Autodesk Fusion 360 part; units mm, degrees
(part 4 of 7)
  spline S126 degree 5 poles (34.1517, -31.5311) (34.1614, -31.5251) (34.1809, -31.5132) (34.2101, -31.4951) (34.2489, -31.471) (34.2972, -31.4407) (34.3454, -31.4102) (34.3934, -31.3796) (34.4413, -31.3489) (34.4891, -31.318) (34.5366, -31.2869) (34.584, -31.2557) (34.6313, -31.2244) (34.6784, -31.1929) (34.7253, -31.1613) (34.772, -31.1295) (34.8186, -31.0975) (34.865, -31.0655) (34.9112, -31.0332) (34.9573, -31.0008) (35.0032, -30.9683) (35.0489, -30.9356) (35.0944, -30.9027) (35.1398, -30.8697) (35.185, -30.8365) (35.23, -30.8032) (35.2748, -30.7697) (35.3194, -30.7361) (35.3638, -30.7023) (35.4081, -30.6683) (35.4521, -30.6342) (35.4959, -30.5999) (35.5396, -30.5654) (35.583, -30.5308) (35.6263, -30.496) (35.6693, -30.4611) (35.7121, -30.426) (35.7548, -30.3907) (35.7971, -30.3552) (35.8393, -30.3196) (35.8813, -30.2838) (35.923, -30.2478) (35.9645, -30.2116) (36.0058, -30.1753) (36.0468, -30.1387) (36.0876, -30.102) (36.1282, -30.0651) (36.1685, -30.028) (36.2085, -29.9907) (36.2483, -29.9533) (36.2879, -29.9156) (36.3271, -29.8777) (36.3661, -29.8396) (36.4048, -29.8014) (36.4432, -29.7629) (36.4775, -29.7281) (36.5039, -29.7009) (36.5226, -29.6815) (36.5338, -29.6698) (36.5375, -29.666) knots -1 -1 -1 -1 -1 -1 -0.985714 -0.971429 -0.957143 -0.942857 -0.928571 -0.914286 -0.9 -0.885714 -0.871429 -0.857143 -0.842857 -0.828571 -0.814286 -0.8 -0.785714 -0.771429 -0.757143 -0.742857 -0.728571 -0.714286 -0.7 -0.685714 -0.671429 -0.657143 -0.642857 -0.628571 -0.614286 -0.6 -0.585714 -0.571429 -0.557143 -0.542857 -0.528571 -0.514286 -0.5 -0.485714 -0.471429 -0.457143 -0.442857 -0.428571 -0.414286 -0.4 -0.385714 -0.371429 -0.357143 -0.342857 -0.328571 -0.314286 -0.3 -0.285714 -0.271429 -0.257143 -0.242857 -0.228571 -0.221564 -0.221564 -0.221564 -0.221564 -0.221564 -0.221564
  spline S127 degree 3 poles (37.152, -29.5804) (37.0958, -29.5474) (37.0338, -29.5257) (36.9049, -29.5074) (36.8392, -29.5109) (36.7308, -29.5383) (36.6874, -29.5561) (36.6066, -29.6031) (36.5698, -29.6322) (36.5375, -29.666) knots 0 0 0 0 0.019532 0.019532 0.039064 0.039064 0.053081 0.053081 0.067098 0.067098 0.067098 0.067098
  arc A64 (37.152, -29.5804) -> (37.5866, -29.8313) centre (54.5011, -0.0327) ccw
  spline S128 degree 3 poles (37.8197, -30.4063) (37.838, -30.3438) (37.8438, -30.2783) (37.8301, -30.1488) (37.8107, -30.086) (37.7576, -29.9876) (37.7298, -29.9498) (37.6644, -29.883) (37.6272, -29.8544) (37.5866, -29.8313) knots 0 0 0 0 0.019532 0.019532 0.039064 0.039064 0.053081 0.053081 0.067098 0.067098 0.067098 0.067098
  spline S129 degree 5 poles (37.8197, -30.4063) (37.8182, -30.4114) (37.8137, -30.4269) (37.8062, -30.4528) (37.7959, -30.4893) (37.7829, -30.5363) (37.7688, -30.5888) (37.755, -30.6415) (37.7415, -30.6943) (37.7283, -30.7472) (37.7155, -30.8003) (37.7029, -30.8535) (37.6906, -30.9068) (37.6787, -30.9603) (37.667, -31.0139) (37.6556, -31.0675) (37.6445, -31.1213) (37.6336, -31.1753) (37.6231, -31.2293) (37.6128, -31.2834) (37.6027, -31.3377) (37.593, -31.392) (37.5835, -31.4465) (37.5742, -31.501) (37.5652, -31.5557) (37.5564, -31.6104) (37.5479, -31.6653) (37.5397, -31.7202) (37.5317, -31.7752) (37.5239, -31.8303) (37.5164, -31.8855) (37.5091, -31.9408) (37.502, -31.9962) (37.4952, -32.0517) (37.4886, -32.1072) (37.4822, -32.1628) (37.4761, -32.2185) (37.4702, -32.2743) (37.4645, -32.3302) (37.459, -32.3861) (37.4538, -32.4422) (37.4488, -32.4982) (37.444, -32.5544) (37.4394, -32.6106) (37.435, -32.667) (37.4308, -32.7233) (37.4269, -32.7798) (37.4232, -32.8363) (37.4196, -32.8929) (37.4163, -32.9495) (37.4132, -33.0062) (37.4103, -33.063) (37.4077, -33.1199) (37.4052, -33.1768) (37.4029, -33.2337) (37.4008, -33.2908) (37.3993, -33.3364) (37.3983, -33.3707) (37.3977, -33.3936) (37.3973, -33.405) knots 0.221564 0.221564 0.221564 0.221564 0.221564 0.221564 0.228571 0.242857 0.257143 0.271429 0.285714 0.3 0.314286 0.328571 0.342857 0.357143 0.371429 0.385714 0.4 0.414286 0.428571 0.442857 0.457143 0.471429 0.485714 0.5 0.514286 0.528571 0.542857 0.557143 0.571429 0.585714 0.6 0.614286 0.628571 0.642857 0.657143 0.671429 0.685714 0.7 0.714286 0.728571 0.742857 0.757143 0.771429 0.785714 0.8 0.814286 0.828571 0.842857 0.857143 0.871429 0.885714 0.9 0.914286 0.928571 0.942857 0.957143 0.971429 0.985714 1 1 1 1 1 1
  arc A65 (37.3973, -33.405) -> (38.4371, -33.9178) centre (54.5011, -0.0327) ccw
  spline S130 degree 5 poles (38.4371, -33.9178) (38.446, -33.9106) (38.4637, -33.8961) (38.4903, -33.8745) (38.5256, -33.8455) (38.5696, -33.8091) (38.6134, -33.7726) (38.6571, -33.736) (38.7005, -33.6993) (38.7438, -33.6624) (38.7869, -33.6254) (38.8298, -33.5883) (38.8726, -33.5511) (38.9152, -33.5137) (38.9575, -33.4762) (38.9997, -33.4386) (39.0418, -33.4009) (39.0836, -33.363) (39.1252, -33.325) (39.1667, -33.2868) (39.2079, -33.2486) (39.249, -33.2102) (39.2898, -33.1717) (39.3305, -33.133) (39.3709, -33.0942) (39.4112, -33.0553) (39.4512, -33.0163) (39.4911, -32.9771) (39.5307, -32.9378) (39.5701, -32.8983) (39.6094, -32.8588) (39.6483, -32.819) (39.6871, -32.7792) (39.7257, -32.7392) (39.764, -32.6991) (39.8021, -32.6588) (39.84, -32.6184) (39.8776, -32.5778) (39.915, -32.5371) (39.9522, -32.4963) (39.9891, -32.4553) (40.0258, -32.4142) (40.0623, -32.3729) (40.0984, -32.3315) (40.1344, -32.2899) (40.17, -32.2482) (40.2054, -32.2063) (40.2405, -32.1643) (40.2754, -32.1221) (40.3099, -32.0797) (40.3442, -32.0372) (40.3782, -31.9946) (40.4118, -31.9517) (40.4452, -31.9087) (40.4783, -31.8655) (40.5077, -31.8266) (40.5303, -31.7962) (40.5464, -31.7745) (40.5559, -31.7615) (40.5591, -31.7572) knots -1 -1 -1 -1 -1 -1 -0.985714 -0.971429 -0.957143 -0.942857 -0.928571 -0.914286 -0.9 -0.885714 -0.871429 -0.857143 -0.842857 -0.828571 -0.814286 -0.8 -0.785714 -0.771429 -0.757143 -0.742857 -0.728571 -0.714286 -0.7 -0.685714 -0.671429 -0.657143 -0.642857 -0.628571 -0.614286 -0.6 -0.585714 -0.571429 -0.557143 -0.542857 -0.528571 -0.514286 -0.5 -0.485714 -0.471429 -0.457143 -0.442857 -0.428571 -0.414286 -0.4 -0.385714 -0.371429 -0.357143 -0.342857 -0.328571 -0.314286 -0.3 -0.285714 -0.271429 -0.257143 -0.242857 -0.228571 -0.221564 -0.221564 -0.221564 -0.221564 -0.221564 -0.221564
  spline S131 degree 3 poles (41.1571, -31.5921) (41.0972, -31.5667) (41.0328, -31.5533) (40.9026, -31.552) (40.838, -31.564) (40.7341, -31.6054) (40.6933, -31.6286) (40.6194, -31.6858) (40.5867, -31.7195) (40.5591, -31.7572) knots 0 0 0 0 0.019532 0.019532 0.039064 0.039064 0.053081 0.053081 0.067098 0.067098 0.067098 0.067098
  arc A66 (41.1571, -31.5921) -> (41.6208, -31.7841) centre (54.5011, -0.0327) ccw
  spline S132 degree 3 poles (41.927, -32.3238) (41.9369, -32.2594) (41.9342, -32.1937) (41.9037, -32.0672) (41.8762, -32.0074) (41.8108, -31.9168) (41.7782, -31.8829) (41.7047, -31.8253) (41.6641, -31.8017) (41.6208, -31.7841) knots 0 0 0 0 0.019532 0.019532 0.039064 0.039064 0.053081 0.053081 0.067098 0.067098 0.067098 0.067098
  spline S133 degree 5 poles (41.927, -32.3238) (41.9262, -32.329) (41.9237, -32.345) (41.9197, -32.3717) (41.9142, -32.4092) (41.9075, -32.4575) (41.9003, -32.5114) (41.8935, -32.5654) (41.887, -32.6196) (41.8809, -32.6738) (41.8751, -32.7281) (41.8695, -32.7824) (41.8643, -32.8369) (41.8594, -32.8915) (41.8549, -32.9461) (41.8506, -33.0008) (41.8466, -33.0556) (41.8429, -33.1105) (41.8394, -33.1654) (41.8363, -33.2204) (41.8334, -33.2755) (41.8308, -33.3307) (41.8285, -33.3859) (41.8265, -33.4412) (41.8247, -33.4966) (41.8231, -33.552) (41.8219, -33.6075) (41.8208, -33.663) (41.8201, -33.7186) (41.8196, -33.7743) (41.8193, -33.83) (41.8193, -33.8858) (41.8195, -33.9416) (41.82, -33.9975) (41.8207, -34.0534) (41.8216, -34.1094) (41.8228, -34.1654) (41.8243, -34.2215) (41.8259, -34.2776) (41.8278, -34.3338) (41.8299, -34.39) (41.8322, -34.4463) (41.8348, -34.5026) (41.8376, -34.5589) (41.8406, -34.6153) (41.8439, -34.6718) (41.8473, -34.7283) (41.851, -34.7848) (41.8549, -34.8413) (41.859, -34.8979) (41.8633, -34.9546) (41.8679, -35.0112) (41.8726, -35.0679) (41.8776, -35.1247) (41.8828, -35.1815) (41.8882, -35.2383) (41.8926, -35.2838) (41.8961, -35.3179) (41.8984, -35.3406) (41.8996, -35.352) knots 0.221564 0.221564 0.221564 0.221564 0.221564 0.221564 0.228571 0.242857 0.257143 0.271429 0.285714 0.3 0.314286 0.328571 0.342857 0.357143 0.371429 0.385714 0.4 0.414286 0.428571 0.442857 0.457143 0.471429 0.485714 0.5 0.514286 0.528571 0.542857 0.557143 0.571429 0.585714 0.6 0.614286 0.628571 0.642857 0.657143 0.671429 0.685714 0.7 0.714286 0.728571 0.742857 0.757143 0.771429 0.785714 0.8 0.814286 0.828571 0.842857 0.857143 0.871429 0.885714 0.9 0.914286 0.928571 0.942857 0.957143 0.971429 0.985714 1 1 1 1 1 1
  arc A67 (41.8996, -35.352) -> (42.9974, -35.7247) centre (54.5011, -0.0327) ccw
  spline S134 degree 5 poles (42.9974, -35.7247) (43.0053, -35.7164) (43.021, -35.6997) (43.0445, -35.6748) (43.0758, -35.6414) (43.1146, -35.5996) (43.1533, -35.5577) (43.1918, -35.5157) (43.2301, -35.4736) (43.2682, -35.4314) (43.3061, -35.3891) (43.3438, -35.3467) (43.3813, -35.3042) (43.4187, -35.2616) (43.4558, -35.2189) (43.4927, -35.1761) (43.5294, -35.1332) (43.566, -35.0902) (43.6023, -35.0471) (43.6384, -35.0039) (43.6743, -34.9606) (43.71, -34.9172) (43.7455, -34.8736) (43.7807, -34.83) (43.8158, -34.7863) (43.8506, -34.7424) (43.8852, -34.6985) (43.9196, -34.6545) (43.9538, -34.6103) (43.9877, -34.5661) (44.0214, -34.5217) (44.0549, -34.4772) (44.0881, -34.4327) (44.1211, -34.388) (44.1539, -34.3432) (44.1864, -34.2983) (44.2187, -34.2533) (44.2507, -34.2082) (44.2825, -34.1629) (44.314, -34.1176) (44.3453, -34.0721) (44.3763, -34.0266) (44.407, -33.9809) (44.4375, -33.9351) (44.4677, -33.8892) (44.4976, -33.8432) (44.5272, -33.797) (44.5565, -33.7508) (44.5856, -33.7044) (44.6143, -33.6579) (44.6427, -33.6113) (44.6708, -33.5645) (44.6986, -33.5177) (44.7261, -33.4707) (44.7533, -33.4235) (44.7773, -33.3811) (44.7958, -33.348) (44.8089, -33.3244) (44.8167, -33.3102) (44.8192, -33.3056) knots -1 -1 -1 -1 -1 -1 -0.985714 -0.971429 -0.957143 -0.942857 -0.928571 -0.914286 -0.9 -0.885714 -0.871429 -0.857143 -0.842857 -0.828571 -0.814286 -0.8 -0.785714 -0.771429 -0.757143 -0.742857 -0.728571 -0.714286 -0.7 -0.685714 -0.671429 -0.657143 -0.642857 -0.628571 -0.614286 -0.6 -0.585714 -0.571429 -0.557143 -0.542857 -0.528571 -0.514286 -0.5 -0.485714 -0.471429 -0.457143 -0.442857 -0.428571 -0.414286 -0.4 -0.385714 -0.371429 -0.357143 -0.342857 -0.328571 -0.314286 -0.3 -0.285714 -0.271429 -0.257143 -0.242857 -0.228571 -0.221564 -0.221564 -0.221564 -0.221564 -0.221564 -0.221564
  spline S135 degree 3 poles (45.3906, -33.0638) (45.3279, -33.0465) (45.2623, -33.0416) (45.1331, -33.0573) (45.0706, -33.0776) (44.9729, -33.1322) (44.9356, -33.1606) (44.8698, -33.227) (44.8417, -33.2646) (44.8192, -33.3056) knots 0 0 0 0 0.019532 0.019532 0.039064 0.039064 0.053081 0.053081 0.067098 0.067098 0.067098 0.067098
  arc A68 (45.3906, -33.0638) -> (45.8754, -33.1937) centre (54.5011, -0.0327) ccw
  spline S136 degree 3 poles (46.2494, -33.6888) (46.2508, -33.6237) (46.2395, -33.5589) (46.1928, -33.4374) (46.1578, -33.3818) (46.081, -33.3004) (46.0444, -33.2711) (45.9639, -33.2235) (45.9206, -33.2055) (45.8754, -33.1937) knots 0 0 0 0 0.019532 0.019532 0.039064 0.039064 0.053081 0.053081 0.067098 0.067098 0.067098 0.067098
  spline S137 degree 5 poles (46.2494, -33.6888) (46.2493, -33.6941) (46.2489, -33.7102) (46.2484, -33.7372) (46.2479, -33.7751) (46.2475, -33.8239) (46.2474, -33.8783) (46.2477, -33.9327) (46.2484, -33.9872) (46.2494, -34.0418) (46.2507, -34.0964) (46.2523, -34.151) (46.2543, -34.2057) (46.2565, -34.2604) (46.2591, -34.3152) (46.262, -34.37) (46.2652, -34.4248) (46.2687, -34.4797) (46.2725, -34.5346) (46.2765, -34.5896) (46.2809, -34.6446) (46.2855, -34.6996) (46.2904, -34.7547) (46.2956, -34.8098) (46.301, -34.8649) (46.3067, -34.92) (46.3127, -34.9752) (46.319, -35.0304) (46.3255, -35.0856) (46.3322, -35.1409) (46.3392, -35.1961) (46.3465, -35.2514) (46.354, -35.3068) (46.3618, -35.3621) (46.3698, -35.4175) (46.378, -35.4728) (46.3865, -35.5282) (46.3952, -35.5836) (46.4042, -35.6391) (46.4134, -35.6945) (46.4228, -35.75) (46.4325, -35.8055) (46.4424, -35.861) (46.4525, -35.9165) (46.4629, -35.972) (46.4735, -36.0275) (46.4843, -36.0831) (46.4953, -36.1386) (46.5065, -36.1942) (46.518, -36.2498) (46.5297, -36.3054) (46.5416, -36.361) (46.5537, -36.4166) (46.566, -36.4722) (46.5786, -36.5278) (46.5913, -36.5834) (46.6017, -36.6279) (46.6096, -36.6613) (46.6149, -36.6835) (46.6175, -36.6947) knots 0.221564 0.221564 0.221564 0.221564 0.221564 0.221564 0.228571 0.242857 0.257143 0.271429 0.285714 0.3 0.314286 0.328571 0.342857 0.357143 0.371429 0.385714 0.4 0.414286 0.428571 0.442857 0.457143 0.471429 0.485714 0.5 0.514286 0.528571 0.542857 0.557143 0.571429 0.585714 0.6 0.614286 0.628571 0.642857 0.657143 0.671429 0.685714 0.7 0.714286 0.728571 0.742857 0.757143 0.771429 0.785714 0.8 0.814286 0.828571 0.842857 0.857143 0.871429 0.885714 0.9 0.914286 0.928571 0.942857 0.957143 0.971429 0.985714 1 1 1 1 1 1
  arc A69 (46.6175, -36.6947) -> (47.7546, -36.9208) centre (54.5011, -0.0327) ccw
  spline S138 degree 5 poles (47.7546, -36.9208) (47.7613, -36.9116) (47.7747, -36.893) (47.7948, -36.8652) (47.8214, -36.8281) (47.8544, -36.7816) (47.8873, -36.735) (47.92, -36.6883) (47.9525, -36.6416) (47.9847, -36.5948) (48.0168, -36.5479) (48.0487, -36.5009) (48.0803, -36.4539) (48.1118, -36.4068) (48.143, -36.3596) (48.174, -36.3124) (48.2048, -36.265) (48.2354, -36.2176) (48.2658, -36.1701) (48.296, -36.1226) (48.3259, -36.0749) (48.3556, -36.0272) (48.3851, -35.9795) (48.4144, -35.9316) (48.4434, -35.8837) (48.4723, -35.8357) (48.5008, -35.7876) (48.5292, -35.7394) (48.5573, -35.6912) (48.5852, -35.6429) (48.6128, -35.5945) (48.6402, -35.546) (48.6673, -35.4975) (48.6942, -35.4489) (48.7208, -35.4002) (48.7472, -35.3515) (48.7734, -35.3026) (48.7992, -35.2537) (48.8248, -35.2047) (48.8502, -35.1557) (48.8752, -35.1065) (48.9, -35.0573) (48.9245, -35.008) (48.9487, -34.9586) (48.9727, -34.9092) (48.9963, -34.8596) (49.0197, -34.81) (49.0427, -34.7603) (49.0654, -34.7106) (49.0878, -34.6607) (49.1099, -34.6108) (49.1317, -34.5608) (49.1532, -34.5107) (49.1743, -34.4605) (49.195, -34.4102) (49.2134, -34.365) (49.2274, -34.3298) (49.2372, -34.3046) (49.2431, -34.2896) (49.245, -34.2846) knots -1 -1 -1 -1 -1 -1 -0.985714 -0.971429 -0.957143 -0.942857 -0.928571 -0.914286 -0.9 -0.885714 -0.871429 -0.857143 -0.842857 -0.828571 -0.814286 -0.8 -0.785714 -0.771429 -0.757143 -0.742857 -0.728571 -0.714286 -0.7 -0.685714 -0.671429 -0.657143 -0.642857 -0.628571 -0.614286 -0.6 -0.585714 -0.571429 -0.557143 -0.542857 -0.528571 -0.514286 -0.5 -0.485714 -0.471429 -0.457143 -0.442857 -0.428571 -0.414286 -0.4 -0.385714 -0.371429 -0.357143 -0.342857 -0.328571 -0.314286 -0.3 -0.285714 -0.271429 -0.257143 -0.242857 -0.228571 -0.221564 -0.221564 -0.221564 -0.221564 -0.221564 -0.221564
  spline S139 degree 3 poles (49.78, -33.9704) (49.7155, -33.9614) (49.6499, -33.9651) (49.5238, -33.9975) (49.4645, -34.0259) (49.3748, -34.0927) (49.3415, -34.1257) (49.2849, -34.2001) (49.2619, -34.2411) (49.245, -34.2846) knots 0 0 0 0 0.019532 0.019532 0.039064 0.039064 0.053081 0.053081 0.067098 0.067098 0.067098 0.067098
  arc A70 (49.78, -33.9704) -> (50.2775, -34.0359) centre (54.5011, -0.0327) ccw
  spline S140 degree 3 poles (50.713, -34.4779) (50.7059, -34.4132) (50.6863, -34.3504) (50.6241, -34.236) (50.5821, -34.1855) (50.4954, -34.1149) (50.4552, -34.0906) (50.3692, -34.0539) (50.3239, -34.0417) (50.2775, -34.0359) knots 0 0 0 0 0.019532 0.019532 0.039064 0.039064 0.053081 0.053081 0.067098 0.067098 0.067098 0.067098
  spline S141 degree 5 poles (50.713, -34.4779) (50.7135, -34.4832) (50.7153, -34.4992) (50.7183, -34.5261) (50.7228, -34.5637) (50.7287, -34.6121) (50.7358, -34.6661) (50.7432, -34.72) (50.7509, -34.7739) (50.759, -34.8279) (50.7675, -34.8818) (50.7762, -34.9358) (50.7853, -34.9898) (50.7947, -35.0437) (50.8044, -35.0977) (50.8144, -35.1516) (50.8247, -35.2056) (50.8353, -35.2596) (50.8463, -35.3135) (50.8575, -35.3675) (50.8689, -35.4214) (50.8807, -35.4754) (50.8928, -35.5293) (50.9051, -35.5833) (50.9177, -35.6372) (50.9306, -35.6911) (50.9437, -35.7451) (50.9571, -35.799) (50.9707, -35.8529) (50.9846, -35.9068) (50.9988, -35.9607) (51.0132, -36.0145) (51.0279, -36.0684) (51.0428, -36.1222) (51.058, -36.1761) (51.0734, -36.2299) (51.089, -36.2837) (51.1049, -36.3375) (51.121, -36.3913) (51.1374, -36.4451) (51.154, -36.4988) (51.1708, -36.5526) (51.1879, -36.6063) (51.2052, -36.66) (51.2227, -36.7137) (51.2404, -36.7674) (51.2584, -36.8211) (51.2765, -36.8747) (51.2949, -36.9283) (51.3136, -36.9819) (51.3324, -37.0355) (51.3515, -37.0891) (51.3707, -37.1426) (51.3902, -37.1961) (51.4099, -37.2497) (51.4298, -37.3031) (51.4459, -37.3459) (51.4581, -37.378) (51.4662, -37.3993) (51.4703, -37.41) knots 0.221564 0.221564 0.221564 0.221564 0.221564 0.221564 0.228571 0.242857 0.257143 0.271429 0.285714 0.3 0.314286 0.328571 0.342857 0.357143 0.371429 0.385714 0.4 0.414286 0.428571 0.442857 0.457143 0.471429 0.485714 0.5 0.514286 0.528571 0.542857 0.557143 0.571429 0.585714 0.6 0.614286 0.628571 0.642857 0.657143 0.671429 0.685714 0.7 0.714286 0.728571 0.742857 0.757143 0.771429 0.785714 0.8 0.814286 0.828571 0.842857 0.857143 0.871429 0.885714 0.9 0.914286 0.928571 0.942857 0.957143 0.971429 0.985714 1 1 1 1 1 1
  arc A71 (51.4703, -37.41) -> (52.6272, -37.4859) centre (54.5011, -0.0327) ccw
  spline S142 degree 5 poles (52.6272, -37.4859) (52.6326, -37.4758) (52.6435, -37.4557) (52.6597, -37.4255) (52.6813, -37.3852) (52.708, -37.3347) (52.7345, -37.2843) (52.7608, -37.2337) (52.7869, -37.1832) (52.8128, -37.1325) (52.8385, -37.0819) (52.8639, -37.0312) (52.8892, -36.9804) (52.9142, -36.9296) (52.939, -36.8787) (52.9636, -36.8278) (52.988, -36.7769) (53.0121, -36.7259) (53.036, -36.6748) (53.0597, -36.6238) (53.0832, -36.5726) (53.1064, -36.5214) (53.1294, -36.4702) (53.1522, -36.419) (53.1748, -36.3676) (53.1971, -36.3163) (53.2191, -36.2649) (53.2409, -36.2134) (53.2625, -36.162) (53.2838, -36.1104) (53.3049, -36.0588) (53.3257, -36.0072) (53.3463, -35.9556) (53.3666, -35.9039) (53.3867, -35.8521) (53.4065, -35.8003) (53.426, -35.7485) (53.4453, -35.6966) (53.4643, -35.6447) (53.483, -35.5928) (53.5014, -35.5408) (53.5195, -35.4887) (53.5374, -35.4367) (53.555, -35.3846) (53.5723, -35.3324) (53.5892, -35.2802) (53.6059, -35.228) (53.6223, -35.1757) (53.6383, -35.1234) (53.654, -35.071) (53.6694, -35.0186) (53.6845, -34.9662) (53.6992, -34.9137) (53.7136, -34.8612) (53.7276, -34.8087) (53.7399, -34.7615) (53.7492, -34.7247) (53.7557, -34.6985) (53.7595, -34.6828) (53.7608, -34.6777) knots -1 -1 -1 -1 -1 -1 -0.985714 -0.971429 -0.957143 -0.942857 -0.928571 -0.914286 -0.9 -0.885714 -0.871429 -0.857143 -0.842857 -0.828571 -0.814286 -0.8 -0.785714 -0.771429 -0.757143 -0.742857 -0.728571 -0.714286 -0.7 -0.685714 -0.671429 -0.657143 -0.642857 -0.628571 -0.614286 -0.6 -0.585714 -0.571429 -0.557143 -0.542857 -0.528571 -0.514286 -0.5 -0.485714 -0.471429 -0.457143 -0.442857 -0.428571 -0.414286 -0.4 -0.385714 -0.371429 -0.357143 -0.342857 -0.328571 -0.314286 -0.3 -0.285714 -0.271429 -0.257143 -0.242857 -0.228571 -0.221564 -0.221564 -0.221564 -0.221564 -0.221564 -0.221564
  spline S143 degree 3 poles (54.2502, -34.2963) (54.185, -34.2958) (54.1205, -34.3081) (53.9996, -34.3566) (53.9446, -34.3924) (53.8644, -34.4704) (53.8356, -34.5075) (53.7892, -34.5887) (53.7719, -34.6323) (53.7608, -34.6777) knots 0 0 0 0 0.019532 0.019532 0.039064 0.039064 0.053081 0.053081 0.067098 0.067098 0.067098 0.067098
  arc A72 (54.2502, -34.2963) -> (54.752, -34.2963) centre (54.5011, -0.0327) ccw
  spline S144 degree 3 poles (55.2414, -34.6777) (55.2259, -34.6144) (55.1983, -34.5548) (55.1217, -34.4495) (55.0735, -34.4048) (54.9783, -34.3461) (54.9352, -34.3273) (54.8452, -34.3021) (54.7987, -34.2959) (54.752, -34.2963) knots 0 0 0 0 0.019532 0.019532 0.039064 0.039064 0.053081 0.053081 0.067098 0.067098 0.067098 0.067098
  spline S145 degree 5 poles (55.2414, -34.6777) (55.2426, -34.6828) (55.2465, -34.6985) (55.253, -34.7247) (55.2623, -34.7615) (55.2745, -34.8087) (55.2886, -34.8612) (55.3029, -34.9137) (55.3177, -34.9662) (55.3327, -35.0186) (55.3481, -35.071) (55.3638, -35.1234) (55.3799, -35.1757) (55.3962, -35.228) (55.4129, -35.2802) (55.4299, -35.3324) (55.4472, -35.3846) (55.4647, -35.4367) (55.4826, -35.4887) (55.5007, -35.5408) (55.5192, -35.5928) (55.5379, -35.6447) (55.5569, -35.6966) (55.5761, -35.7485) (55.5957, -35.8003) (55.6155, -35.8521) (55.6355, -35.9039) (55.6558, -35.9556) (55.6764, -36.0072) (55.6972, -36.0588) (55.7183, -36.1104) (55.7396, -36.162) (55.7612, -36.2134) (55.783, -36.2649) (55.8051, -36.3163) (55.8274, -36.3676) (55.8499, -36.419) (55.8727, -36.4702) (55.8957, -36.5214) (55.9189, -36.5726) (55.9424, -36.6238) (55.9661, -36.6748) (55.99, -36.7259) (56.0142, -36.7769) (56.0385, -36.8278) (56.0631, -36.8787) (56.0879, -36.9296) (56.113, -36.9804) (56.1382, -37.0312) (56.1637, -37.0819) (56.1893, -37.1325) (56.2152, -37.1832) (56.2413, -37.2337) (56.2676, -37.2843) (56.2941, -37.3347) (56.3209, -37.3852) (56.3424, -37.4255) (56.3586, -37.4557) (56.3695, -37.4758) (56.375, -37.4859) knots 0.221564 0.221564 0.221564 0.221564 0.221564 0.221564 0.228571 0.242857 0.257143 0.271429 0.285714 0.3 0.314286 0.328571 0.342857 0.357143 0.371429 0.385714 0.4 0.414286 0.428571 0.442857 0.457143 0.471429 0.485714 0.5 0.514286 0.528571 0.542857 0.557143 0.571429 0.585714 0.6 0.614286 0.628571 0.642857 0.657143 0.671429 0.685714 0.7 0.714286 0.728571 0.742857 0.757143 0.771429 0.785714 0.8 0.814286 0.828571 0.842857 0.857143 0.871429 0.885714 0.9 0.914286 0.928571 0.942857 0.957143 0.971429 0.985714 1 1 1 1 1 1
  arc A73 (56.375, -37.4859) -> (57.5318, -37.41) centre (54.5011, -0.0327) ccw
  spline S146 degree 5 poles (57.5318, -37.41) (57.5359, -37.3993) (57.5441, -37.378) (57.5562, -37.3459) (57.5723, -37.3031) (57.5922, -37.2497) (57.6119, -37.1961) (57.6314, -37.1426) (57.6507, -37.0891) (57.6697, -37.0355) (57.6886, -36.9819) (57.7072, -36.9283) (57.7256, -36.8747) (57.7438, -36.8211) (57.7617, -36.7674) (57.7795, -36.7137) (57.797, -36.66) (57.8143, -36.6063) (57.8313, -36.5526) (57.8482, -36.4988) (57.8647, -36.4451) (57.8811, -36.3913) (57.8972, -36.3375) (57.9131, -36.2837) (57.9288, -36.2299) (57.9442, -36.1761) (57.9593, -36.1222) (57.9742, -36.0684) (57.9889, -36.0145) (58.0033, -35.9607) (58.0175, -35.9068) (58.0314, -35.8529) (58.0451, -35.799) (58.0585, -35.7451) (58.0716, -35.6911) (58.0845, -35.6372) (58.0971, -35.5833) (58.1094, -35.5293) (58.1214, -35.4754) (58.1332, -35.4214) (58.1447, -35.3675) (58.1559, -35.3135) (58.1668, -35.2596) (58.1774, -35.2056) (58.1877, -35.1516) (58.1978, -35.0977) (58.2075, -35.0437) (58.2169, -34.9898) (58.2259, -34.9358) (58.2347, -34.8818) (58.2431, -34.8279) (58.2512, -34.7739) (58.2589, -34.72) (58.2663, -34.6661) (58.2734, -34.6121) (58.2794, -34.5637) (58.2838, -34.5261) (58.2868, -34.4992) (58.2886, -34.4832) (58.2892, -34.4779) knots -1 -1 -1 -1 -1 -1 -0.985714 -0.971429 -0.957143 -0.942857 -0.928571 -0.914286 -0.9 -0.885714 -0.871429 -0.857143 -0.842857 -0.828571 -0.814286 -0.8 -0.785714 -0.771429 -0.757143 -0.742857 -0.728571 -0.714286 -0.7 -0.685714 -0.671429 -0.657143 -0.642857 -0.628571 -0.614286 -0.6 -0.585714 -0.571429 -0.557143 -0.542857 -0.528571 -0.514286 -0.5 -0.485714 -0.471429 -0.457143 -0.442857 -0.428571 -0.414286 -0.4 -0.385714 -0.371429 -0.357143 -0.342857 -0.328571 -0.314286 -0.3 -0.285714 -0.271429 -0.257143 -0.242857 -0.228571 -0.221564 -0.221564 -0.221564 -0.221564 -0.221564 -0.221564
  spline S147 degree 3 poles (58.7246, -34.0359) (58.66, -34.0439) (58.5976, -34.0645) (58.4841, -34.1284) (58.4342, -34.1711) (58.3649, -34.2589) (58.3412, -34.2994) (58.3058, -34.3859) (58.2942, -34.4314) (58.2892, -34.4779) knots 0 0 0 0 0.019532 0.019532 0.039064 0.039064 0.053081 0.053081 0.067098 0.067098 0.067098 0.067098
  arc A74 (58.7246, -34.0359) -> (59.2221, -33.9704) centre (54.5011, -0.0327) ccw
  spline S148 degree 3 poles (59.7571, -34.2846) (59.7335, -34.2239) (59.6983, -34.1684) (59.6087, -34.074) (59.555, -34.036) (59.453, -33.9903) (59.4079, -33.9772) (59.3154, -33.964) (59.2684, -33.964) (59.2221, -33.9704) knots 0 0 0 0 0.019532 0.019532 0.039064 0.039064 0.053081 0.053081 0.067098 0.067098 0.067098 0.067098
  spline S149 degree 5 poles (59.7571, -34.2846) (59.759, -34.2896) (59.7649, -34.3046) (59.7748, -34.3298) (59.7888, -34.365) (59.8071, -34.4102) (59.8279, -34.4605) (59.849, -34.5107) (59.8704, -34.5608) (59.8922, -34.6108) (59.9143, -34.6607) (59.9367, -34.7106) (59.9594, -34.7603) (59.9825, -34.81) (60.0058, -34.8596) (60.0295, -34.9092) (60.0534, -34.9586) (60.0776, -35.008) (60.1021, -35.0573) (60.1269, -35.1065) (60.152, -35.1557) (60.1773, -35.2047) (60.2029, -35.2537) (60.2288, -35.3026) (60.2549, -35.3515) (60.2813, -35.4002) (60.3079, -35.4489) (60.3348, -35.4975) (60.362, -35.546) (60.3894, -35.5945) (60.417, -35.6429) (60.4449, -35.6912) (60.473, -35.7394) (60.5013, -35.7876) (60.5299, -35.8357) (60.5587, -35.8837) (60.5877, -35.9316) (60.617, -35.9795) (60.6465, -36.0272) (60.6762, -36.0749) (60.7062, -36.1226) (60.7363, -36.1701) (60.7667, -36.2176) (60.7973, -36.265) (60.8281, -36.3124) (60.8591, -36.3596) (60.8904, -36.4068) (60.9218, -36.4539) (60.9535, -36.5009) (60.9853, -36.5479) (61.0174, -36.5948) (61.0497, -36.6416) (61.0821, -36.6883) (61.1148, -36.735) (61.1477, -36.7816) (61.1808, -36.8281) (61.2074, -36.8652) (61.2274, -36.893) (61.2408, -36.9116) (61.2476, -36.9208) knots 0.221564 0.221564 0.221564 0.221564 0.221564 0.221564 0.228571 0.242857 0.257143 0.271429 0.285714 0.3 0.314286 0.328571 0.342857 0.357143 0.371429 0.385714 0.4 0.414286 0.428571 0.442857 0.457143 0.471429 0.485714 0.5 0.514286 0.528571 0.542857 0.557143 0.571429 0.585714 0.6 0.614286 0.628571 0.642857 0.657143 0.671429 0.685714 0.7 0.714286 0.728571 0.742857 0.757143 0.771429 0.785714 0.8 0.814286 0.828571 0.842857 0.857143 0.871429 0.885714 0.9 0.914286 0.928571 0.942857 0.957143 0.971429 0.985714 1 1 1 1 1 1
  arc A75 (61.2476, -36.9208) -> (62.3846, -36.6947) centre (54.5011, -0.0327) ccw
  spline S150 degree 5 poles (62.3846, -36.6947) (62.3873, -36.6835) (62.3926, -36.6613) (62.4004, -36.6279) (62.4108, -36.5834) (62.4236, -36.5278) (62.4361, -36.4722) (62.4484, -36.4166) (62.4606, -36.361) (62.4725, -36.3054) (62.4842, -36.2498) (62.4956, -36.1942) (62.5069, -36.1386) (62.5179, -36.0831) (62.5287, -36.0275) (62.5393, -35.972) (62.5496, -35.9165) (62.5597, -35.861) (62.5696, -35.8055) (62.5793, -35.75) (62.5887, -35.6945) (62.5979, -35.6391) (62.6069, -35.5836) (62.6156, -35.5282) (62.6241, -35.4728) (62.6324, -35.4175) (62.6404, -35.3621) (62.6481, -35.3068) (62.6556, -35.2514) (62.6629, -35.1961) (62.6699, -35.1409) (62.6767, -35.0856) (62.6832, -35.0304) (62.6894, -34.9752) (62.6954, -34.92) (62.7011, -34.8649) (62.7066, -34.8098) (62.7117, -34.7547) (62.7167, -34.6996) (62.7213, -34.6446) (62.7256, -34.5896) (62.7297, -34.5346) (62.7335, -34.4797) (62.737, -34.4248) (62.7401, -34.37) (62.743, -34.3152) (62.7456, -34.2604) (62.7479, -34.2057) (62.7498, -34.151) (62.7515, -34.0964) (62.7528, -34.0418) (62.7538, -33.9872) (62.7544, -33.9327) (62.7547, -33.8783) (62.7546, -33.8239) (62.7543, -33.7751) (62.7537, -33.7372) (62.7532, -33.7102) (62.7529, -33.6941) (62.7528, -33.6888) knots -1 -1 -1 -1 -1 -1 -0.985714 -0.971429 -0.957143 -0.942857 -0.928571 -0.914286 -0.9 -0.885714 -0.871429 -0.857143 -0.842857 -0.828571 -0.814286 -0.8 -0.785714 -0.771429 -0.757143 -0.742857 -0.728571 -0.714286 -0.7 -0.685714 -0.671429 -0.657143 -0.642857 -0.628571 -0.614286 -0.6 -0.585714 -0.571429 -0.557143 -0.542857 -0.528571 -0.514286 -0.5 -0.485714 -0.471429 -0.457143 -0.442857 -0.428571 -0.414286 -0.4 -0.385714 -0.371429 -0.357143 -0.342857 -0.328571 -0.314286 -0.3 -0.285714 -0.271429 -0.257143 -0.242857 -0.228571 -0.221564 -0.221564 -0.221564 -0.221564 -0.221564 -0.221564
  spline S151 degree 3 poles (63.1268, -33.1937) (63.0638, -33.2101) (63.0046, -33.2387) (62.9004, -33.3168) (62.8565, -33.3657) (62.7992, -33.4618) (62.781, -33.5051) (62.7572, -33.5954) (62.7517, -33.642) (62.7528, -33.6888) knots 0 0 0 0 0.019532 0.019532 0.039064 0.039064 0.053081 0.053081 0.067098 0.067098 0.067098 0.067098
  arc A76 (63.1268, -33.1937) -> (63.6115, -33.0638) centre (54.5011, -0.0327) ccw
  spline S152 degree 3 poles (64.1829, -33.3056) (64.1516, -33.2485) (64.1095, -33.198) (64.0082, -33.1161) (63.9501, -33.0855) (63.843, -33.0534) (63.7965, -33.0464) (63.7031, -33.0454) (63.6565, -33.0514) (63.6115, -33.0638) knots 0 0 0 0 0.019532 0.019532 0.039064 0.039064 0.053081 0.053081 0.067098 0.067098 0.067098 0.067098
  spline S153 degree 5 poles (64.1829, -33.3056) (64.1855, -33.3102) (64.1933, -33.3244) (64.2063, -33.348) (64.2248, -33.3811) (64.2489, -33.4235) (64.276, -33.4707) (64.3035, -33.5177) (64.3313, -33.5645) (64.3594, -33.6113) (64.3878, -33.6579) (64.4166, -33.7044) (64.4456, -33.7508) (64.4749, -33.797) (64.5046, -33.8432) (64.5345, -33.8892) (64.5647, -33.9351) (64.5951, -33.9809) (64.6259, -34.0266) (64.6568, -34.0721) (64.6881, -34.1176) (64.7196, -34.1629) (64.7514, -34.2082) (64.7834, -34.2533) (64.8157, -34.2983) (64.8482, -34.3432) (64.881, -34.388) (64.914, -34.4327) (64.9472, -34.4772) (64.9807, -34.5217) (65.0144, -34.5661) (65.0484, -34.6103) (65.0825, -34.6545) (65.1169, -34.6985) (65.1515, -34.7424) (65.1864, -34.7863) (65.2214, -34.83) (65.2567, -34.8736) (65.2922, -34.9172) (65.3279, -34.9606) (65.3638, -35.0039) (65.3999, -35.0471) (65.4362, -35.0902) (65.4727, -35.1332) (65.5094, -35.1761) (65.5464, -35.2189) (65.5835, -35.2616) (65.6208, -35.3042) (65.6583, -35.3467) (65.6961, -35.3891) (65.734, -35.4314) (65.7721, -35.4736) (65.8104, -35.5157) (65.8488, -35.5577) (65.8875, -35.5996) (65.9264, -35.6414) (65.9576, -35.6748) (65.9811, -35.6997) (65.9968, -35.7164) (66.0047, -35.7247) knots 0.221564 0.221564 0.221564 0.221564 0.221564 0.221564 0.228571 0.242857 0.257143 0.271429 0.285714 0.3 0.314286 0.328571 0.342857 0.357143 0.371429 0.385714 0.4 0.414286 0.428571 0.442857 0.457143 0.471429 0.485714 0.5 0.514286 0.528571 0.542857 0.557143 0.571429 0.585714 0.6 0.614286 0.628571 0.642857 0.657143 0.671429 0.685714 0.7 0.714286 0.728571 0.742857 0.757143 0.771429 0.785714 0.8 0.814286 0.828571 0.842857 0.857143 0.871429 0.885714 0.9 0.914286 0.928571 0.942857 0.957143 0.971429 0.985714 1 1 1 1 1 1
  arc A77 (66.0047, -35.7247) -> (67.1025, -35.352) centre (54.5011, -0.0327) ccw
  spline S154 degree 5 poles (67.1025, -35.352) (67.1037, -35.3406) (67.106, -35.3179) (67.1095, -35.2838) (67.114, -35.2383) (67.1194, -35.1815) (67.1245, -35.1247) (67.1295, -35.0679) (67.1343, -35.0112) (67.1388, -34.9546) (67.1431, -34.8979) (67.1472, -34.8413) (67.1511, -34.7848) (67.1548, -34.7283) (67.1583, -34.6718) (67.1615, -34.6153) (67.1645, -34.5589) (67.1673, -34.5026) (67.1699, -34.4463) (67.1722, -34.39) (67.1743, -34.3338) (67.1762, -34.2776) (67.1779, -34.2215) (67.1793, -34.1654) (67.1805, -34.1094) (67.1814, -34.0534) (67.1822, -33.9975) (67.1826, -33.9416) (67.1829, -33.8858) (67.1828, -33.83) (67.1826, -33.7743) (67.1821, -33.7186) (67.1813, -33.663) (67.1803, -33.6075) (67.179, -33.552) (67.1775, -33.4966) (67.1757, -33.4412) (67.1736, -33.3859) (67.1713, -33.3307) (67.1687, -33.2755) (67.1658, -33.2204) (67.1627, -33.1654) (67.1593, -33.1105) (67.1556, -33.0556) (67.1516, -33.0008) (67.1473, -32.9461) (67.1427, -32.8915) (67.1378, -32.8369) (67.1326, -32.7824) (67.1271, -32.7281) (67.1213, -32.6738) (67.1151, -32.6196) (67.1086, -32.5654) (67.1018, -32.5114) (67.0947, -32.4575) (67.0879, -32.4092) (67.0825, -32.3717) (67.0784, -32.345) (67.076, -32.329) (67.0752, -32.3238) knots -1 -1 -1 -1 -1 -1 -0.985714 -0.971429 -0.957143 -0.942857 -0.928571 -0.914286 -0.9 -0.885714 -0.871429 -0.857143 -0.842857 -0.828571 -0.814286 -0.8 -0.785714 -0.771429 -0.757143 -0.742857 -0.728571 -0.714286 -0.7 -0.685714 -0.671429 -0.657143 -0.642857 -0.628571 -0.614286 -0.6 -0.585714 -0.571429 -0.557143 -0.542857 -0.528571 -0.514286 -0.5 -0.485714 -0.471429 -0.457143 -0.442857 -0.428571 -0.414286 -0.4 -0.385714 -0.371429 -0.357143 -0.342857 -0.328571 -0.314286 -0.3 -0.285714 -0.271429 -0.257143 -0.242857 -0.228571 -0.221564 -0.221564 -0.221564 -0.221564 -0.221564 -0.221564
  spline S155 degree 3 poles (67.3814, -31.7841) (67.321, -31.8086) (67.2661, -31.8446) (67.173, -31.9357) (67.1358, -31.9899) (67.0916, -32.0927) (67.0792, -32.1379) (67.0674, -32.2306) (67.068, -32.2776) (67.0752, -32.3238) knots 0 0 0 0 0.019532 0.019532 0.039064 0.039064 0.053081 0.053081 0.067098 0.067098 0.067098 0.067098
  arc A78 (67.3814, -31.7841) -> (67.845, -31.5921) centre (54.5011, -0.0327) ccw
  spline S156 degree 3 poles (68.4431, -31.7572) (68.4046, -31.7046) (68.3562, -31.6601) (68.2452, -31.5922) (68.1835, -31.5694) (68.0731, -31.5516) (68.0262, -31.5506) (67.9334, -31.5618) (67.888, -31.5739) (67.845, -31.5921) knots 0 0 0 0 0.019532 0.019532 0.039064 0.039064 0.053081 0.053081 0.067098 0.067098 0.067098 0.067098
  spline S157 degree 5 poles (68.4431, -31.7572) (68.4462, -31.7615) (68.4558, -31.7745) (68.4718, -31.7962) (68.4945, -31.8266) (68.5239, -31.8655) (68.5569, -31.9087) (68.5903, -31.9517) (68.624, -31.9946) (68.658, -32.0372) (68.6922, -32.0797) (68.7268, -32.1221) (68.7616, -32.1643) (68.7967, -32.2063) (68.8321, -32.2482) (68.8678, -32.2899) (68.9037, -32.3315) (68.9399, -32.3729) (68.9763, -32.4142) (69.013, -32.4553) (69.0499, -32.4963) (69.0871, -32.5371) (69.1245, -32.5778) (69.1621, -32.6184) (69.2, -32.6588) (69.2381, -32.6991) (69.2765, -32.7392) (69.315, -32.7792) (69.3538, -32.819) (69.3928, -32.8588) (69.432, -32.8983) (69.4714, -32.9378) (69.5111, -32.9771) (69.5509, -33.0163) (69.591, -33.0553) (69.6312, -33.0942) (69.6717, -33.133) (69.7123, -33.1717) (69.7532, -33.2102) (69.7942, -33.2486) (69.8355, -33.2868) (69.8769, -33.325) (69.9186, -33.363) (69.9604, -33.4009) (70.0024, -33.4386) (70.0446, -33.4762) (70.087, -33.5137) (70.1295, -33.5511) (70.1723, -33.5883) (70.2152, -33.6254) (70.2583, -33.6624) (70.3016, -33.6993) (70.3451, -33.736) (70.3887, -33.7726) (70.4325, -33.8091) (70.4765, -33.8455) (70.5118, -33.8745) (70.5384, -33.8961) (70.5561, -33.9106) (70.565, -33.9178) knots 0.221564 0.221564 0.221564 0.221564 0.221564 0.221564 0.228571 0.242857 0.257143 0.271429 0.285714 0.3 0.314286 0.328571 0.342857 0.357143 0.371429 0.385714 0.4 0.414286 0.428571 0.442857 0.457143 0.471429 0.485714 0.5 0.514286 0.528571 0.542857 0.557143 0.571429 0.585714 0.6 0.614286 0.628571 0.642857 0.657143 0.671429 0.685714 0.7 0.714286 0.728571 0.742857 0.757143 0.771429 0.785714 0.8 0.814286 0.828571 0.842857 0.857143 0.871429 0.885714 0.9 0.914286 0.928571 0.942857 0.957143 0.971429 0.985714 1 1 1 1 1 1
  arc A79 (70.565, -33.9178) -> (71.6048, -33.405) centre (54.5011, -0.0327) ccw
  spline S158 degree 5 poles (71.6048, -33.405) (71.6045, -33.3936) (71.6038, -33.3707) (71.6028, -33.3364) (71.6013, -33.2908) (71.5992, -33.2337) (71.597, -33.1768) (71.5945, -33.1199) (71.5918, -33.063) (71.5889, -33.0062) (71.5858, -32.9495) (71.5825, -32.8929) (71.579, -32.8363) (71.5752, -32.7798) (71.5713, -32.7233) (71.5671, -32.667) (71.5628, -32.6106) (71.5582, -32.5544) (71.5534, -32.4982) (71.5484, -32.4422) (71.5431, -32.3861) (71.5377, -32.3302) (71.532, -32.2743) (71.5261, -32.2185) (71.5199, -32.1628) (71.5135, -32.1072) (71.507, -32.0517) (71.5001, -31.9962) (71.4931, -31.9408) (71.4858, -31.8855) (71.4782, -31.8303) (71.4705, -31.7752) (71.4625, -31.7202) (71.4542, -31.6653) (71.4457, -31.6104) (71.4369, -31.5557) (71.4279, -31.501) (71.4187, -31.4465) (71.4092, -31.392) (71.3994, -31.3377) (71.3894, -31.2834) (71.3791, -31.2293) (71.3685, -31.1753) (71.3577, -31.1213) (71.3465, -31.0675) (71.3352, -31.0139) (71.3235, -30.9603) (71.3115, -30.9068) (71.2992, -30.8535) (71.2867, -30.8003) (71.2738, -30.7472) (71.2606, -30.6943) (71.2471, -30.6415) (71.2333, -30.5888) (71.2192, -30.5363) (71.2062, -30.4893) (71.1959, -30.4528) (71.1884, -30.4269) (71.1839, -30.4114) (71.1824, -30.4063) knots -1 -1 -1 -1 -1 -1 -0.985714 -0.971429 -0.957143 -0.942857 -0.928571 -0.914286 -0.9 -0.885714 -0.871429 -0.857143 -0.842857 -0.828571 -0.814286 -0.8 -0.785714 -0.771429 -0.757143 -0.742857 -0.728571 -0.714286 -0.7 -0.685714 -0.671429 -0.657143 -0.642857 -0.628571 -0.614286 -0.6 -0.585714 -0.571429 -0.557143 -0.542857 -0.528571 -0.514286 -0.5 -0.485714 -0.471429 -0.457143 -0.442857 -0.428571 -0.414286 -0.4 -0.385714 -0.371429 -0.357143 -0.342857 -0.328571 -0.314286 -0.3 -0.285714 -0.271429 -0.257143 -0.242857 -0.228571 -0.221564 -0.221564 -0.221564 -0.221564 -0.221564 -0.221564
  spline S159 degree 3 poles (71.4156, -29.8313) (71.3589, -29.8634) (71.3091, -29.9063) (71.2288, -30.0088) (71.199, -30.0674) (71.1685, -30.175) (71.1622, -30.2215) (71.1626, -30.3149) (71.1693, -30.3614) (71.1824, -30.4063) knots 0 0 0 0 0.019532 0.019532 0.039064 0.039064 0.053081 0.053081 0.067098 0.067098 0.067098 0.067098
  arc A80 (71.4156, -29.8313) -> (71.8502, -29.5804) centre (54.5011, -0.0327) ccw
  spline S160 degree 3 poles (72.4647, -29.666) (72.4197, -29.6189) (72.3659, -29.5811) (72.2469, -29.5282) (72.1828, -29.5136) (72.071, -29.5104) (72.0244, -29.5156) (71.9339, -29.5388) (71.8905, -29.5567) (71.8502, -29.5804) knots 0 0 0 0 0.019532 0.019532 0.039064 0.039064 0.053081 0.053081 0.067098 0.067098 0.067098 0.067098
  spline S161 degree 5 poles (72.4647, -29.666) (72.4683, -29.6698) (72.4795, -29.6815) (72.4983, -29.7009) (72.5247, -29.7281) (72.5589, -29.7629) (72.5973, -29.8014) (72.636, -29.8396) (72.675, -29.8777) (72.7143, -29.9156) (72.7538, -29.9533) (72.7936, -29.9907) (72.8336, -30.028) (72.8739, -30.0651) (72.9145, -30.102) (72.9553, -30.1387) (72.9963, -30.1753) (73.0376, -30.2116) (73.0791, -30.2478) (73.1209, -30.2838) (73.1628, -30.3196) (73.205, -30.3552) (73.2474, -30.3907) (73.29, -30.426) (73.3328, -30.4611) (73.3759, -30.496) (73.4191, -30.5308) (73.4626, -30.5654) (73.5062, -30.5999) (73.55, -30.6342) (73.5941, -30.6683) (73.6383, -30.7023) (73.6828, -30.7361) (73.7274, -30.7697) (73.7722, -30.8032) (73.8172, -30.8365) (73.8623, -30.8697) (73.9077, -30.9027) (73.9532, -30.9356) (73.9989, -30.9683) (74.0448, -31.0008) (74.0909, -31.0332) (74.1371, -31.0655) (74.1835, -31.0975) (74.2301, -31.1295) (74.2769, -31.1613) (74.3238, -31.1929) (74.3709, -31.2244) (74.4181, -31.2557) (74.4655, -31.2869) (74.5131, -31.318) (74.5608, -31.3489) (74.6087, -31.3796) (74.6567, -31.4102) (74.7049, -31.4407) (74.7533, -31.471) (74.7921, -31.4951) (74.8213, -31.5132) (74.8407, -31.5251) (74.8505, -31.5311) knots 0.221564 0.221564 0.221564 0.221564 0.221564 0.221564 0.228571 0.242857 0.257143 0.271429 0.285714 0.3 0.314286 0.328571 0.342857 0.357143 0.371429 0.385714 0.4 0.414286 0.428571 0.442857 0.457143 0.471429 0.485714 0.5 0.514286 0.528571 0.542857 0.557143 0.571429 0.585714 0.6 0.614286 0.628571 0.642857 0.657143 0.671429 0.685714 0.7 0.714286 0.728571 0.742857 0.757143 0.771429 0.785714 0.8 0.814286 0.828571 0.842857 0.857143 0.871429 0.885714 0.9 0.914286 0.928571 0.942857 0.957143 0.971429 0.985714 1 1 1 1 1 1
  arc A81 (74.8505, -31.5311) -> (75.8144, -30.887) centre (54.5011, -0.0327) ccw
  spline S162 degree 5 poles (75.8144, -30.887) (75.8126, -30.8757) (75.809, -30.8532) (75.8035, -30.8193) (75.7961, -30.7742) (75.7866, -30.7179) (75.7769, -30.6618) (75.767, -30.6057) (75.7569, -30.5497) (75.7466, -30.4937) (75.7361, -30.4379) (75.7255, -30.3822) (75.7146, -30.3265) (75.7035, -30.271) (75.6922, -30.2155) (75.6808, -30.1602) (75.6691, -30.1049) (75.6572, -30.0498) (75.6451, -29.9947) (75.6328, -29.9398) (75.6203, -29.8849) (75.6076, -29.8302) (75.5946, -29.7755) (75.5815, -29.721) (75.5681, -29.6666) (75.5546, -29.6122) (75.5408, -29.558) (75.5268, -29.5039) (75.5125, -29.45) (75.4981, -29.3961) (75.4834, -29.3423) (75.4685, -29.2887) (75.4534, -29.2352) (75.438, -29.1818) (75.4224, -29.1286) (75.4066, -29.0754) (75.3906, -29.0224) (75.3743, -28.9695) (75.3577, -28.9168) (75.341, -28.8642) (75.3239, -28.8117) (75.3066, -28.7594) (75.2891, -28.7072) (75.2713, -28.6552) (75.2533, -28.6033) (75.235, -28.5515) (75.2164, -28.4999) (75.1976, -28.4485) (75.1784, -28.3972) (75.159, -28.3461) (75.1394, -28.2952) (75.1194, -28.2444) (75.0991, -28.1938) (75.0786, -28.1434) (75.0577, -28.0932) (75.0387, -28.0483) (75.0237, -28.0135) (75.0129, -27.9887) (75.0064, -27.9739) (75.0043, -27.9691) knots -1 -1 -1 -1 -1 -1 -0.985714 -0.971429 -0.957143 -0.942857 -0.928571 -0.914286 -0.9 -0.885714 -0.871429 -0.857143 -0.842857 -0.828571 -0.814286 -0.8 -0.785714 -0.771429 -0.757143 -0.742857 -0.728571 -0.714286 -0.7 -0.685714 -0.671429 -0.657143 -0.642857 -0.628571 -0.614286 -0.6 -0.585714 -0.571429 -0.557143 -0.542857 -0.528571 -0.514286 -0.5 -0.485714 -0.471429 -0.457143 -0.442857 -0.428571 -0.414286 -0.4 -0.385714 -0.371429 -0.357143 -0.342857 -0.328571 -0.314286 -0.3 -0.285714 -0.271429 -0.257143 -0.242857 -0.228571 -0.221564 -0.221564 -0.221564 -0.221564 -0.221564 -0.221564
  spline S163 degree 3 poles (75.1604, -27.3686) (75.1084, -27.4078) (75.0646, -27.4569) (74.9983, -27.5689) (74.9764, -27.6309) (74.9603, -27.7416) (74.9601, -27.7885) (74.9727, -27.8811) (74.9854, -27.9263) (75.0043, -27.9691) knots 0 0 0 0 0.019532 0.019532 0.039064 0.039064 0.053081 0.053081 0.067098 0.067098 0.067098 0.067098
  arc A82 (75.1604, -27.3686) -> (75.5585, -27.0631) centre (54.5011, -0.0327) ccw
  spline S164 degree 3 poles (76.1789, -27.0677) (76.1281, -27.0269) (76.0699, -26.9965) (75.945, -26.9596) (75.8796, -26.9535) (75.7683, -26.9649) (75.7228, -26.9761) (75.636, -27.011) (75.5953, -27.0344) (75.5585, -27.0631) knots 0 0 0 0 0.019532 0.019532 0.039064 0.039064 0.053081 0.053081 0.067098 0.067098 0.067098 0.067098
  spline S165 degree 5 poles (76.1789, -27.0677) (76.183, -27.0711) (76.1957, -27.0812) (76.2168, -27.098) (76.2465, -27.1215) (76.285, -27.1515) (76.3281, -27.1846) (76.3715, -27.2175) (76.4151, -27.2502) (76.459, -27.2826) (76.5031, -27.3148) (76.5474, -27.3468) (76.592, -27.3785) (76.6368, -27.41) (76.6818, -27.4413) (76.727, -27.4724) (76.7725, -27.5033) (76.8182, -27.5339) (76.864, -27.5644) (76.9101, -27.5946) (76.9564, -27.6246) (77.0029, -27.6544) (77.0495, -27.6841) (77.0964, -27.7135) (77.1434, -27.7427) (77.1907, -27.7718) (77.2381, -27.8006) (77.2857, -27.8293) (77.3334, -27.8577) (77.3814, -27.886) (77.4295, -27.9141) (77.4778, -27.942) (77.5262, -27.9697) (77.5749, -27.9972) (77.6237, -28.0246) (77.6726, -28.0517) (77.7217, -28.0787) (77.771, -28.1055) (77.8204, -28.1322) (77.87, -28.1586) (77.9198, -28.1849) (77.9697, -28.211) (78.0197, -28.2369) (78.0699, -28.2627) (78.1203, -28.2883) (78.1708, -28.3137) (78.2214, -28.3389) (78.2722, -28.364) (78.3231, -28.3889) (78.3742, -28.4137) (78.4254, -28.4382) (78.4768, -28.4626) (78.5283, -28.4869) (78.5799, -28.5109) (78.6316, -28.5348) (78.6835, -28.5586) (78.7252, -28.5774) (78.7564, -28.5915) (78.7773, -28.6009) (78.7878, -28.6055) knots 0.221564 0.221564 0.221564 0.221564 0.221564 0.221564 0.228571 0.242857 0.257143 0.271429 0.285714 0.3 0.314286 0.328571 0.342857 0.357143 0.371429 0.385714 0.4 0.414286 0.428571 0.442857 0.457143 0.471429 0.485714 0.5 0.514286 0.528571 0.542857 0.557143 0.571429 0.585714 0.6 0.614286 0.628571 0.642857 0.657143 0.671429 0.685714 0.7 0.714286 0.728571 0.742857 0.757143 0.771429 0.785714 0.8 0.814286 0.828571 0.842857 0.857143 0.871429 0.885714 0.9 0.914286 0.928571 0.942857 0.957143 0.971429 0.985714 1 1 1 1 1 1
  arc A83 (78.7878, -28.6055) -> (79.6594, -27.8411) centre (54.5011, -0.0327) ccw
  spline S166 degree 5 poles (79.6594, -27.8411) (79.6561, -27.8302) (79.6496, -27.8082) (79.6397, -27.7754) (79.6265, -27.7317) (79.6097, -27.6771) (79.5928, -27.6227) (79.5756, -27.5684) (79.5583, -27.5141) (79.5408, -27.46) (79.5232, -27.4061) (79.5053, -27.3522) (79.4873, -27.2985) (79.469, -27.2448) (79.4506, -27.1913) (79.432, -27.1379) (79.4132, -27.0847) (79.3942, -27.0316) (79.375, -26.9785) (79.3557, -26.9257) (79.3361, -26.8729) (79.3164, -26.8203) (79.2964, -26.7678) (79.2763, -26.7155) (79.2559, -26.6632) (79.2354, -26.6111) (79.2146, -26.5592) (79.1937, -26.5074) (79.1725, -26.4557) (79.1512, -26.4042) (79.1296, -26.3528) (79.1078, -26.3016) (79.0858, -26.2505) (79.0636, -26.1996) (79.0412, -26.1488) (79.0186, -26.0982) (78.9958, -26.0478) (78.9727, -25.9975) (78.9494, -25.9473) (78.9259, -25.8974) (78.9022, -25.8476) (78.8782, -25.798) (78.854, -25.7485) (78.8296, -25.6992) (78.805, -25.6501) (78.7801, -25.6012) (78.7549, -25.5525) (78.7295, -25.504) (78.7039, -25.4556) (78.678, -25.4075) (78.6518, -25.3596) (78.6254, -25.3119) (78.5987, -25.2643) (78.5717, -25.217) (78.5445, -25.17) (78.5198, -25.1279) (78.5004, -25.0954) (78.4864, -25.0722) (78.478, -25.0584) (78.4753, -25.0539) knots -1 -1 -1 -1 -1 -1 -0.985714 -0.971429 -0.957143 -0.942857 -0.928571 -0.914286 -0.9 -0.885714 -0.871429 -0.857143 -0.842857 -0.828571 -0.814286 -0.8 -0.785714 -0.771429 -0.757143 -0.742857 -0.728571 -0.714286 -0.7 -0.685714 -0.671429 -0.657143 -0.642857 -0.628571 -0.614286 -0.6 -0.585714 -0.571429 -0.557143 -0.542857 -0.528571 -0.514286 -0.5 -0.485714 -0.471429 -0.457143 -0.442857 -0.428571 -0.414286 -0.4 -0.385714 -0.371429 -0.357143 -0.342857 -0.328571 -0.314286 -0.3 -0.285714 -0.271429 -0.257143 -0.242857 -0.228571 -0.221564 -0.221564 -0.221564 -0.221564 -0.221564 -0.221564
  spline S167 degree 3 poles (78.5517, -24.4381) (78.5053, -24.4838) (78.4683, -24.5382) (78.4172, -24.6579) (78.4036, -24.7222) (78.402, -24.834) (78.4079, -24.8806) (78.4325, -24.9708) (78.451, -25.0139) (78.4753, -25.0539) knots 0 0 0 0 0.019532 0.019532 0.039064 0.039064 0.053081 0.053081 0.067098 0.067098 0.067098 0.067098
  arc A84 (78.5517, -24.4381) -> (78.9065, -24.0833) centre (54.5011, -0.0327) ccw
  spline S168 degree 3 poles (79.5222, -24.0069) (79.4666, -23.9731) (79.4049, -23.9505) (79.2762, -23.9302) (79.2106, -23.9327) (79.1018, -23.9585) (79.058, -23.9756) (78.9766, -24.0215) (78.9393, -24.05) (78.9065, -24.0833) knots 0 0 0 0 0.019532 0.019532 0.039064 0.039064 0.053081 0.053081 0.067098 0.067098 0.067098 0.067098
  spline S169 degree 5 poles (79.5222, -24.0069) (79.5268, -24.0097) (79.5406, -24.018) (79.5637, -24.032) (79.5963, -24.0514) (79.6383, -24.0761) (79.6854, -24.1034) (79.7327, -24.1303) (79.7802, -24.157) (79.8279, -24.1834) (79.8759, -24.2096) (79.924, -24.2355) (79.9723, -24.2611) (80.0209, -24.2865) (80.0696, -24.3117) (80.1185, -24.3366) (80.1676, -24.3613) (80.2169, -24.3857) (80.2663, -24.4099) (80.3159, -24.4338) (80.3657, -24.4576) (80.4157, -24.4811) (80.4658, -24.5043) (80.5161, -24.5274) (80.5666, -24.5502) (80.6172, -24.5729) (80.668, -24.5953) (80.7189, -24.6175) (80.77, -24.6394) (80.8212, -24.6612) (80.8726, -24.6828) (80.9241, -24.7041) (80.9758, -24.7253) (81.0276, -24.7462) (81.0795, -24.767) (81.1316, -24.7875) (81.1838, -24.8079) (81.2362, -24.828) (81.2887, -24.848) (81.3413, -24.8677) (81.394, -24.8873) (81.4469, -24.9067) (81.4999, -24.9258) (81.5531, -24.9448) (81.6063, -24.9636) (81.6597, -24.9822) (81.7132, -25.0007) (81.7668, -25.0189) (81.8206, -25.0369) (81.8744, -25.0548) (81.9284, -25.0725) (81.9825, -25.09) (82.0367, -25.1073) (82.091, -25.1244) (82.1455, -25.1413) (82.2, -25.1581) (82.2438, -25.1714) (82.2766, -25.1812) (82.2985, -25.1878) (82.3095, -25.191) knots 0.221564 0.221564 0.221564 0.221564 0.221564 0.221564 0.228571 0.242857 0.257143 0.271429 0.285714 0.3 0.314286 0.328571 0.342857 0.357143 0.371429 0.385714 0.4 0.414286 0.428571 0.442857 0.457143 0.471429 0.485714 0.5 0.514286 0.528571 0.542857 0.557143 0.571429 0.585714 0.6 0.614286 0.628571 0.642857 0.657143 0.671429 0.685714 0.7 0.714286 0.728571 0.742857 0.757143 0.771429 0.785714 0.8 0.814286 0.828571 0.842857 0.857143 0.871429 0.885714 0.9 0.914286 0.928571 0.942857 0.957143 0.971429 0.985714 1 1 1 1 1 1
  arc A85 (82.3095, -25.191) -> (83.0739, -24.3194) centre (54.5011, -0.0327) ccw
  spline S170 degree 5 poles (83.0739, -24.3194) (83.0692, -24.309) (83.0599, -24.2881) (83.0458, -24.2568) (83.027, -24.2152) (83.0032, -24.1633) (82.9793, -24.1115) (82.9552, -24.0599) (82.931, -24.0084) (82.9066, -23.9571) (82.882, -23.9058) (82.8573, -23.8548) (82.8324, -23.8038) (82.8073, -23.7531) (82.7821, -23.7024) (82.7567, -23.6519) (82.7311, -23.6016) (82.7053, -23.5514) (82.6794, -23.5013) (82.6533, -23.4514) (82.627, -23.4017) (82.6005, -23.3521) (82.5739, -23.3026) (82.5471, -23.2534) (82.5201, -23.2042) (82.4929, -23.1553) (82.4656, -23.1065) (82.4381, -23.0579) (82.4103, -23.0094) (82.3824, -22.9611) (82.3544, -22.913) (82.3261, -22.8651) (82.2976, -22.8173) (82.269, -22.7697) (82.2401, -22.7223) (82.2111, -22.6751) (82.1819, -22.628) (82.1524, -22.5812) (82.1228, -22.5345) (82.093, -22.488) (82.063, -22.4417) (82.0327, -22.3957) (82.0023, -22.3498) (81.9716, -22.3041) (81.9408, -22.2587) (81.9097, -22.2134) (81.8784, -22.1684) (81.8469, -22.1236) (81.8152, -22.079) (81.7832, -22.0347) (81.751, -21.9906) (81.7186, -21.9467) (81.6859, -21.9031) (81.653, -21.8597) (81.6199, -21.8166) (81.5899, -21.7781) (81.5664, -21.7484) (81.5495, -21.7273) (81.5394, -21.7147) (81.5361, -21.7105) knots -1 -1 -1 -1 -1 -1 -0.985714 -0.971429 -0.957143 -0.942857 -0.928571 -0.914286 -0.9 -0.885714 -0.871429 -0.857143 -0.842857 -0.828571 -0.814286 -0.8 -0.785714 -0.771429 -0.757143 -0.742857 -0.728571 -0.714286 -0.7 -0.685714 -0.671429 -0.657143 -0.642857 -0.628571 -0.614286 -0.6 -0.585714 -0.571429 -0.557143 -0.542857 -0.528571 -0.514286 -0.5 -0.485714 -0.471429 -0.457143 -0.442857 -0.428571 -0.414286 -0.4 -0.385714 -0.371429 -0.357143 -0.342857 -0.328571 -0.314286 -0.3 -0.285714 -0.271429 -0.257143 -0.242857 -0.228571 -0.221564 -0.221564 -0.221564 -0.221564 -0.221564 -0.221564